body (Autodesk Fusion 360 design; units mm, degrees)
Autodesk Fusion 360 part; units mm, degrees
sketch "스케치1" plane through (0, 0, 0) normal (0, 1, 0) x (1, 0, 0)
  line L0 (0, 0) -> (100, 0)
  line L1 (100, 0) -> (100, -50)
  line L2 (100, -50) -> (0, -50)
  line L3 (0, -50) -> (0, 0)
  dimension "d1" = 100
  dimension "d2" = 50
  constraint horizontal L0
  constraint vertical L1
  constraint horizontal L2
  constraint vertical L3
  constraint coincident L0.start L3.end
  measures "d1" distance of L0.start L0.end
  measures "d2" distance of L0.start L2.end
extrude "돌출1" add sketch "스케치1" along normal blind 4.5 in component "Component"
sketch "스케치2" plane through (0, 0, 0) normal (0, -1, 0) x (1, 0, 0)
  line L0 (100, 50) -> (0, 50)
  line L1 (0, 50) -> (0, 0)
  line L2 (0, 0) -> (100, 0)
  line L3 (100, 0) -> (100, 50)
  circle A0 centre (5, 25) radius 1.5
  circle A1 centre (67, 25) radius 1.5
  circle A2 centre (29.8, 25) radius 1.5
  circle A3 centre (42.2, 25) radius 1.5
  line L4 (72, 50) -> (72, 0)
  dimension "d5" = 3
  dimension "d6" = 5
  dimension "d7" = 25
  dimension "d8" = 3
  dimension "d9" = 62
  dimension "d10" = 3
  dimension "d11" = 24.8
  dimension "d12" = 3
  dimension "d13" = 24.8
  dimension "d14" = 5
  constraint horizontal A0.centre A2.centre
  constraint coincident L0 L4.start
  constraint coincident L2 L4.end
  constraint perpendicular L2 L4
  measures "d5" diameter of A0
  measures "d6" distance of L1 A0.centre
  measures "d7" distance of L2 A0.centre
  measures "d8" diameter of A1
  measures "d9" distance of A0.centre A1.centre
  measures "d10" diameter of A2
  measures "d11" distance of A0.centre A2.centre
  measures "d12" diameter of A3
  measures "d13" distance of A1.centre A3.centre
  measures "d14" distance of A1.centre L4
extrude "돌출2" cut sketch "스케치2" against normal blind 4.5 contours A0 | A1 | A2 | A3 in component "Component"
extrude "돌출3" cut sketch "스케치2" against normal blind 100 contours L0 L2 L3 L4 in component "Component"
sketch "스케치3" plane through (0, 58.5, 0) normal (0, -1, 0) x (1, 0, 0)
  line L0 (72, 0) -> (72, 50)
  line L1 (72, 50) -> (0, 50)
  line L2 (0, 50) -> (0, 0)
  line L3 (0, 0) -> (72, 0)
  circle A0 centre (67, 25) radius 1.5
  circle A1 centre (5, 25) radius 1.5
  circle A2 centre (42.2, 25) radius 1.5
  circle A3 centre (29.8, 25) radius 1.5
  line L4 (67, 25) -> (73.125, 35.6088)
  line L5 (67, 25) -> (79.25, 25) construction
  line L6 (67, 25) -> (76.875, 7.896)
  line L7 (67, 25) -> (86.75, 25) construction
  line L8 (67, 25) -> (67, 5.25)
  line L9 (67, 25) -> (67, 37.25)
  line L10 (67, 25) -> (51, 25)
  arc A4 (67, 37.25) -> (67, 5.25) centre (66.5605, 21.25) ccw
  circle A5 centre (67, 25) radius 12.25
  circle A6 centre (67, 25) radius 19.75
  dimension "d19" = 60
  dimension "d20" = 12.25
  dimension "d21" = 60
  dimension "d22" = 19.75
  dimension "d23" = 19.75
  dimension "d24" = 12.25
  dimension "d25" = 16
  constraint horizontal L5
  constraint coincident A0.centre L4.start
  constraint horizontal L7
  constraint perpendicular L5 L8
  constraint perpendicular L5 L9
  constraint perpendicular L8 L10
  constraint coincident L10.end A4
  constraint coincident L4.end A5
  constraint concentric A5 A6
  constraint coincident L6.end A6
  measures "d19" angle of L4 L5
  measures "d20" distance of A0.centre L4.end
  measures "d21" angle of L6 L7
  measures "d22" distance of A0.centre L6.end
  measures "d23" distance of A0.centre L8.end
  measures "d24" distance of A0.centre L9.end
  measures "d25" distance of A0.centre L10.end
extrude "돌출1'" [suppressed] in component "Component'"
sketch "스케치4" plane through (0, 53, 0) normal (0, -1, 0) x (1, 0, 0)
  circle A0 centre (67, 25) radius 1.5
  arc A1 (73.125, 14.3912) -> (67, 37.25) centre (67, 25) ccw
  arc A2 (67, 37.25) -> (62.4338, 5.7851) centre (66.5605, 21.25) ccw
  arc A3 (62.4338, 5.7851) -> (76.875, 7.896) centre (67, 25) ccw
  line L0 (76.875, 7.896) -> (73.125, 14.3912)
  line L1 (67, 37.25) -> (66, 37.25)
  line L2 (66, 37.25) -> (66, 38.25)
  line L3 (66, 38.25) -> (67, 38.25)
  line L4 (67, 38.25) -> (67, 37.25)
  line L5 (67, 37.25) -> (68, 37.25)
  line L6 (68, 37.25) -> (68, 38.25)
  line L7 (68, 38.25) -> (67, 38.25)
  line L8 (67, 38.25) -> (67, 37.25)
  line L9 (66, 38.25) -> (68, 38.25)
  line L10 (68, 38.25) -> (68, 36.25)
  line L11 (68, 36.25) -> (66, 36.25)
  line L12 (66, 36.25) -> (66, 38.25)
  dimension "d28" = 1
  dimension "d29" = 1
  dimension "d30" = 1
  dimension "d31" = 2
  dimension "d32" = 2
  constraint horizontal L1
  constraint vertical L2
  constraint horizontal L3
  constraint vertical L4
  constraint coincident A1.end A2.start
  constraint horizontal L5
  constraint vertical L6
  constraint horizontal L7
  constraint vertical L8
  constraint horizontal L9
  constraint vertical L10
  constraint horizontal L11
  constraint vertical L12
  measures "d28" distance of A1.end L1.end
  measures "d29" distance of A1.end L3.end
  measures "d30" distance of A1.end L3.end
  measures "d31" distance of L2.end L6.end
  measures "d32" distance of L2.end L11.end
sketch "스케치5" plane through (0, 0, 50) normal (0, 0, 1) x (-1, 0, 0)
  line L0 (-72, -58.5) -> (-72, -63)
  line L1 (-72, -63) -> (0, -63)
  line L2 (0, -63) -> (0, -58.5)
  line L3 (0, -58.5) -> (-72, -58.5)
  line L4 (0, -63) -> (-20, -63)
  line L5 (-20, -63) -> (-20, 9)
  line L6 (-20, 9) -> (0, 9)
  line L7 (0, 9) -> (0, -63)
  line L8 (-72, -63) -> (-52, -63)
  line L9 (-52, -63) -> (-52, 9)
  line L10 (-52, 9) -> (-72, 9)
  line L11 (-72, 9) -> (-72, -63)
  dimension "d33" = 20
  dimension "d34" = 72
  dimension "d35" = 20
  dimension "d36" = 72
  constraint horizontal L4
  constraint vertical L5
  constraint horizontal L6
  constraint vertical L7
  constraint coincident L1.end L2.start
  constraint horizontal L8
  constraint vertical L9
  constraint horizontal L10
  constraint vertical L11
  constraint coincident L0.end L1.start
  measures "d33" distance of L1.end L4.end
  measures "d34" distance of L1.end L6.end
  measures "d35" distance of L0.end L8.end
  measures "d36" distance of L0.end L10.end
extrude "돌출1''" [suppressed] in component "Component''"
sketch "스케치6" plane through (0, -55.5322, 0) normal (0, 1, 0) x (-1, 0, 0)
  arc A0 (-21.5259, 27.2332) -> (-21.5259, 28.3332) centre (-20.5733, 27.7832) ccw
  line L0 (-21.5259, 27.2332) -> (-22.7233, 27.2332)
  line L1 (-22.7233, 27.2332) -> (-22.7233, 22.5332)
  arc A1 (-22.7233, 22.5332) -> (-21.8733, 21.6832) centre (-21.8733, 22.5332) ccw
  line L2 (-21.8733, 21.6832) -> (-17.0733, 21.6832)
  arc A2 (-17.9233, 22.5332) -> (-17.0733, 21.6832) centre (-17.0733, 22.5332) ccw
  line L3 (-17.9233, 22.5332) -> (-17.9233, 33.0332)
  arc A3 (-17.0733, 33.8832) -> (-17.9233, 33.0332) centre (-17.0733, 33.0332) ccw
  line L4 (-17.0733, 33.8832) -> (-21.8733, 33.8832)
  arc A4 (-21.8733, 33.8832) -> (-22.7233, 33.0332) centre (-21.8733, 33.0332) ccw
  line L5 (-22.7233, 33.0332) -> (-22.7233, 28.3332)
  line L6 (-22.7233, 28.3332) -> (-21.5259, 28.3332)
  line L7 (14.3767, 39.8832) -> (-27.7233, 39.8832)
  line L8 (-27.7233, 39.8832) -> (-27.7233, 15.6832)
  line L9 (-27.7233, 15.6832) -> (14.3767, 15.6832)
  line L10 (14.3767, 15.6832) -> (14.3767, 39.8832)
  line L11 (8.5267, 33.8832) -> (3.7267, 33.8832)
  line L12 (9.3767, 22.5332) -> (9.3767, 27.2332)
  line L13 (3.7267, 21.6832) -> (8.5267, 21.6832)
  line L14 (4.6267, 33.8832) -> (-17.964, 33.8832)
  line L15 (-17.964, 33.8832) -> (-17.964, 21.6832)
  line L16 (-17.964, 21.6832) -> (4.6267, 21.6832)
  line L17 (4.6267, 21.6832) -> (4.6267, 33.8832)
  point P0 (4.6267, 33.8832)
  point P1 (4.5189, 21.6832)
  point P2 (-18.0719, 33.8832)
  point P3 (-17.964, 21.6832)
  dimension "d39" = 6
  dimension "d40" = 5
  dimension "d41" = 6
  dimension "d42" = 5
  dimension "d43" = 0.9
  constraint horizontal L7
  constraint vertical L8
  constraint horizontal L9
  constraint vertical L10
  constraint coincident L11 P0
  constraint coincident L13 P1
  constraint coincident L4 P2
  constraint coincident L2 P3
  constraint horizontal L14
  constraint vertical L15
  constraint horizontal L16
  constraint vertical L17
  constraint coincident P3 L15.end
  constraint coincident P0 L14.start
  measures "d39" distance of L7 L11
  measures "d40" distance of L10 L12
  measures "d41" distance of L9 L13
  measures "d42" distance of L1.end L8
  measures "d43" distance of L11.end P0
extrude "돌출1'''" [suppressed] in component "Component'''"
sketch "스케치7" plane through (0, -9, 0) normal (0, -1, 0) x (1, 0, 0)
  line L0 (72, 0) -> (72, 50)
  line L1 (72, 50) -> (0, 50)
  line L2 (0, 50) -> (0, 0)
  line L3 (0, 0) -> (72, 0)
  circle A0 centre (67, 25) radius 1.5
  circle A1 centre (5, 25) radius 1.5
  circle A2 centre (42.2, 25) radius 1.5
  circle A3 centre (29.8, 25) radius 1.5
  circle A4 centre (5, 25) radius 2
  circle A5 centre (29.8, 25) radius 2
  circle A6 centre (42.2, 25) radius 2
  circle A7 centre (67, 25) radius 2
  dimension "d46" = 4
  dimension "d47" = 4
  dimension "d48" = 4
  dimension "d49" = 4
  constraint concentric A1 A4
  constraint concentric A3 A5
  constraint concentric A2 A6
  constraint concentric A0 A7
  measures "d46" diameter of A4
  measures "d47" diameter of A5
  measures "d48" diameter of A6
  measures "d49" diameter of A7
extrude "돌출4" [suppressed] in component "Component"
sketch "스케치8" plane through (0, 51.75, 0) normal (0, -1, 0) x (1, 0, 0)
  circle A0 centre (67, 25) radius 1.5
  arc A1 (73.125, 14.3912) -> (67, 37.25) centre (67, 25) ccw
  arc A2 (67, 37.25) -> (62.4338, 5.7851) centre (66.5605, 21.25) ccw
  arc A3 (62.4338, 5.7851) -> (76.875, 7.896) centre (67, 25) ccw
  line L0 (76.875, 7.896) -> (73.125, 14.3912)
  circle A4 centre (67, 25) radius 2
  dimension "d52" = 4
  constraint concentric A0 A4
  measures "d52" diameter of A4
extrude "돌출2'" [suppressed] in component "Component'"
sketch "스케치9" plane through (0, -42.0822, 0) normal (0, 1, 0) x (-1, 0, 0)
  line L0 (0.3767, 21.3332) -> (0.3767, 24.9036)
  arc A0 (0.3767, 24.9036) -> (0.6858, 25.1332) centre (-1.5233, 27.7832) ccw
  line L1 (0.6858, 25.1332) -> (12.6359, 25.7862)
  arc A1 (12.6359, 25.7862) -> (12.6359, 29.7802) centre (12.5267, 27.7832) ccw
  line L2 (12.6359, 29.7802) -> (0.6858, 30.4332)
  arc A2 (0.6858, 30.4332) -> (0.3767, 30.6629) centre (-1.5233, 27.7832) ccw
  line L3 (0.3767, 30.6629) -> (0.3767, 34.2332)
  arc A3 (0.3767, 34.2332) -> (-3.4233, 34.2332) centre (-1.5233, 34.2332) ccw
  line L4 (-3.4233, 34.2332) -> (-3.4233, 31.0786)
  line L5 (-3.4233, 31.0786) -> (-18.1496, 29.7754)
  arc A4 (-18.1496, 29.7754) -> (-18.1496, 25.791) centre (-17.9733, 27.7832) ccw
  line L6 (-18.1496, 25.791) -> (-3.4233, 24.4879)
  line L7 (-3.4233, 24.4879) -> (-3.4233, 21.3332)
  arc A5 (-3.4233, 21.3332) -> (0.3767, 21.3332) centre (-1.5233, 21.3332) ccw
  circle A6 centre (-16.3733, 27.7832) radius 0.6
  circle A7 centre (-18.3733, 27.7832) radius 0.6
  circle A8 centre (-14.3733, 27.7832) radius 0.6
  circle A9 centre (-12.3733, 27.7832) radius 0.6
  circle A10 centre (-10.3733, 27.7832) radius 0.6
  circle A11 centre (-8.3733, 27.7832) radius 0.6
  circle A12 centre (-6.3733, 27.7832) radius 0.6
  circle A13 centre (2.9267, 27.7832) radius 0.6
  circle A14 centre (4.9267, 27.7832) radius 0.6
  circle A15 centre (6.9267, 27.7832) radius 0.6
  circle A16 centre (8.9267, 27.7832) radius 0.6
  circle A17 centre (12.9267, 27.7832) radius 0.6
  circle A18 centre (10.9267, 27.7832) radius 0.6
  circle A19 centre (-1.5233, 27.7832) radius 2.3
  circle A20 centre (-1.5233, 23.3332) radius 0.6
  circle A21 centre (-1.5233, 21.3332) radius 0.6
  circle A22 centre (-1.5233, 32.2332) radius 0.6
  circle A23 centre (-1.5233, 34.2332) radius 0.6
  line L8 (-21.5233, 37.7832) -> (18.4767, 37.7832)
  line L9 (18.4767, 37.7832) -> (18.4767, 17.7832)
  line L10 (18.4767, 17.7832) -> (-21.5233, 17.7832)
  line L11 (-21.5233, 17.7832) -> (-21.5233, 37.7832)
  line L12 (-21.5233, 37.7832) -> (18.4767, 17.7832) construction
  line L13 (18.4767, 37.7832) -> (-21.5233, 17.7832) construction
  line L14 (3.4767, 10.2832) -> (-6.5233, 10.2832)
  line L15 (-6.5233, 10.2832) -> (-6.5233, 45.2832)
  line L16 (-6.5233, 45.2832) -> (3.4767, 45.2832)
  line L17 (3.4767, 45.2832) -> (3.4767, 10.2832)
  line L18 (3.4767, 10.2832) -> (-6.5233, 45.2832) construction
  line L19 (-6.5233, 10.2832) -> (3.4767, 45.2832) construction
  circle A24 centre (-1.5233, 27.7832) radius 2
  circle A25 centre (-1.5233, 15.1832) radius 2
  circle A26 centre (-1.5233, 40.3832) radius 2
  point P0 (-1.5233, 27.7832)
  point P1 (-1.5233, 27.7832)
  point P2 (-1.5233, 21.3332)
  dimension "d55" = 40
  dimension "d56" = 20
  dimension "d57" = 10
  dimension "d58" = 35
  dimension "d59" = 4
  dimension "d60" = 4
  dimension "d61" = 4
  dimension "d62" = 12.6
  dimension "d63" = 12.6
  constraint horizontal L8
  constraint perpendicular L8 L9
  constraint parallel L8 L10
  constraint parallel L9 L11
  constraint coincident L12 P1
  constraint coincident L13 P1
  constraint coincident P1 P0
  constraint horizontal L14
  constraint perpendicular L14 L15
  constraint parallel L14 L16
  constraint parallel L15 L17
  constraint coincident L18 P1
  constraint coincident L19 P1
  constraint concentric A0 A24
  constraint vertical A25.centre P2
  constraint vertical P1 A26.centre
  measures "d55" distance of L9.end L10.end
  measures "d56" distance of L8.end L9.end
  measures "d57" distance of L15.end L16.end
  measures "d58" distance of L14.end L15.end
  measures "d59" diameter of A24
  measures "d60" diameter of A25
  measures "d61" diameter of A26
  measures "d62" distance of P1 A26.centre
  measures "d63" distance of P1 A25.centre
extrude "돌출1''''" [suppressed] in component "Component''''"
sketch "스케치10" plane through (0, -37.5822, 0) normal (0, 1, 0) x (-1, 0, 0)
  arc A0 (-3.4233, 21.3332) -> (0.3767, 21.3332) centre (-1.5233, 21.3332) ccw
  line L0 (-3.4233, 21.3332) -> (-3.4233, 24.4879)
  line L1 (-3.4233, 24.4879) -> (-18.1496, 25.791)
  arc A1 (-18.1496, 29.7754) -> (-18.1496, 25.791) centre (-17.9733, 27.7832) ccw
  line L2 (-18.1496, 29.7754) -> (-3.4233, 31.0786)
  line L3 (-3.4233, 31.0786) -> (-3.4233, 34.2332)
  arc A2 (0.3767, 34.2332) -> (-3.4233, 34.2332) centre (-1.5233, 34.2332) ccw
  line L4 (0.3767, 34.2332) -> (0.3767, 30.6629)
  arc A3 (0.6858, 30.4332) -> (0.3767, 30.6629) centre (-1.5233, 27.7832) ccw
  line L5 (0.6858, 30.4332) -> (12.6359, 29.7802)
  arc A4 (12.6359, 25.7862) -> (12.6359, 29.7802) centre (12.5267, 27.7832) ccw
  line L6 (12.6359, 25.7862) -> (0.6858, 25.1332)
  arc A5 (0.3767, 24.9036) -> (0.6858, 25.1332) centre (-1.5233, 27.7832) ccw
  line L7 (0.3767, 24.9036) -> (0.3767, 21.3332)
  circle A6 centre (-1.5233, 15.1832) radius 2
  circle A7 centre (-1.5233, 40.3832) radius 2
  line L8 (3.4767, 45.2832) -> (-6.5233, 45.2832)
  line L9 (-6.5233, 45.2832) -> (-6.5233, 37.7832)
  line L10 (-6.5233, 37.7832) -> (-21.5233, 37.7832)
  line L11 (-21.5233, 37.7832) -> (-21.5233, 17.7832)
  line L12 (-21.5233, 17.7832) -> (-6.5233, 17.7832)
  line L13 (-6.5233, 17.7832) -> (-6.5233, 10.2832)
  line L14 (-6.5233, 10.2832) -> (3.4767, 10.2832)
  line L15 (3.4767, 10.2832) -> (3.4767, 17.7832)
  line L16 (3.4767, 17.7832) -> (18.4767, 17.7832)
  line L17 (18.4767, 17.7832) -> (18.4767, 37.7832)
  line L18 (18.4767, 37.7832) -> (3.4767, 37.7832)
  line L19 (3.4767, 37.7832) -> (3.4767, 45.2832)
  line L20 (-6.5233, 45.2832) -> (3.4767, 45.2832)
  line L21 (3.4767, 45.2832) -> (3.4767, 10.2832)
  line L22 (3.4767, 10.2832) -> (-6.5233, 10.2832)
  line L23 (-6.5233, 10.2832) -> (-6.5233, 45.2832)
  circle A8 centre (-1.5233, 40.3832) radius 2
  circle A9 centre (-1.5233, 15.1832) radius 2
  constraint horizontal L20
  constraint vertical L21
  constraint horizontal L22
  constraint vertical L23
  constraint coincident L14.end L15.start
  constraint coincident L8.end L9.start
  constraint concentric A7 A8
  constraint concentric A6 A9
extrude "돌출1'''''" [suppressed] in component "Component'''''"
sketch "스케치11" plane through (0, -44.0822, 0) normal (0, -1, 0) x (1, 0, 0)
  arc A0 (-0.3767, 21.3332) -> (3.4233, 21.3332) centre (1.5233, 21.3332) ccw
  line L0 (-0.3767, 21.3332) -> (-0.3767, 24.9036)
  arc A1 (-0.6858, 25.1332) -> (-0.3767, 24.9036) centre (1.5233, 27.7832) ccw
  line L1 (-0.6858, 25.1332) -> (-12.6359, 25.7862)
  arc A2 (-12.6359, 29.7802) -> (-12.6359, 25.7862) centre (-12.5267, 27.7832) ccw
  line L2 (-12.6359, 29.7802) -> (-0.6858, 30.4332)
  arc A3 (-0.3767, 30.6629) -> (-0.6858, 30.4332) centre (1.5233, 27.7832) ccw
  line L3 (-0.3767, 30.6629) -> (-0.3767, 34.2332)
  arc A4 (3.4233, 34.2332) -> (-0.3767, 34.2332) centre (1.5233, 34.2332) ccw
  line L4 (3.4233, 34.2332) -> (3.4233, 31.0786)
  line L5 (3.4233, 31.0786) -> (18.1496, 29.7754)
  arc A5 (18.1496, 25.791) -> (18.1496, 29.7754) centre (17.9733, 27.7832) ccw
  line L6 (18.1496, 25.791) -> (3.4233, 24.4879)
  line L7 (3.4233, 24.4879) -> (3.4233, 21.3332)
  circle A6 centre (1.5233, 15.1832) radius 2
  circle A7 centre (1.5233, 40.3832) radius 2
  line L8 (6.5233, 45.2832) -> (-3.4767, 45.2832)
  line L9 (-3.4767, 45.2832) -> (-3.4767, 37.7832)
  line L10 (-3.4767, 37.7832) -> (-18.4767, 37.7832)
  line L11 (-18.4767, 37.7832) -> (-18.4767, 17.7832)
  line L12 (-18.4767, 17.7832) -> (-3.4767, 17.7832)
  line L13 (-3.4767, 17.7832) -> (-3.4767, 10.2832)
  line L14 (-3.4767, 10.2832) -> (6.5233, 10.2832)
  line L15 (6.5233, 10.2832) -> (6.5233, 17.7832)
  line L16 (6.5233, 17.7832) -> (21.5233, 17.7832)
  line L17 (21.5233, 17.7832) -> (21.5233, 37.7832)
  line L18 (21.5233, 37.7832) -> (6.5233, 37.7832)
  line L19 (6.5233, 37.7832) -> (6.5233, 45.2832)
  line L20 (-18.4767, 37.7832) -> (21.5233, 37.7832)
  line L21 (21.5233, 37.7832) -> (21.5233, 17.7832)
  line L22 (21.5233, 17.7832) -> (-18.4767, 17.7832)
  line L23 (-18.4767, 17.7832) -> (-18.4767, 37.7832)
  circle A8 centre (1.5233, 27.7832) radius 3.45
  constraint horizontal L20
  constraint vertical L21
  constraint horizontal L22
  constraint vertical L23
  constraint coincident L16.end L17.start
  constraint coincident L10.end L11.start
  constraint concentric A1 A8
  constraint coincident L0.end A8
extrude "돌출1''''''" [suppressed] in component "3T"
sketch "스케치12" plane through (0, -44.0822, 0) normal (0, -1, 0) x (1, 0, 0)
  arc A0 (-0.3767, 21.3332) -> (3.4233, 21.3332) centre (1.5233, 21.3332) ccw
  line L0 (-0.3767, 21.3332) -> (-0.3767, 24.9036)
  arc A1 (-0.6858, 25.1332) -> (-0.3767, 24.9036) centre (1.5233, 27.7832) ccw
  line L1 (-0.6858, 25.1332) -> (-12.6359, 25.7862)
  arc A2 (-12.6359, 29.7802) -> (-12.6359, 25.7862) centre (-12.5267, 27.7832) ccw
  line L2 (-12.6359, 29.7802) -> (-0.6858, 30.4332)
  arc A3 (-0.3767, 30.6629) -> (-0.6858, 30.4332) centre (1.5233, 27.7832) ccw
  line L3 (-0.3767, 30.6629) -> (-0.3767, 34.2332)
  arc A4 (3.4233, 34.2332) -> (-0.3767, 34.2332) centre (1.5233, 34.2332) ccw
  line L4 (3.4233, 34.2332) -> (3.4233, 31.0786)
  line L5 (3.4233, 31.0786) -> (18.1496, 29.7754)
  arc A5 (18.1496, 25.791) -> (18.1496, 29.7754) centre (17.9733, 27.7832) ccw
  line L6 (18.1496, 25.791) -> (3.4233, 24.4879)
  line L7 (3.4233, 24.4879) -> (3.4233, 21.3332)
  circle A6 centre (1.5233, 15.1832) radius 2
  circle A7 centre (1.5233, 40.3832) radius 2
  line L8 (6.5233, 45.2832) -> (-3.4767, 45.2832)
  line L9 (-3.4767, 45.2832) -> (-3.4767, 37.7832)
  line L10 (-3.4767, 37.7832) -> (-18.4767, 37.7832)
  line L11 (-18.4767, 37.7832) -> (-18.4767, 17.7832)
  line L12 (-18.4767, 17.7832) -> (-3.4767, 17.7832)
  line L13 (-3.4767, 17.7832) -> (-3.4767, 10.2832)
  line L14 (-3.4767, 10.2832) -> (6.5233, 10.2832)
  line L15 (6.5233, 10.2832) -> (6.5233, 17.7832)
  line L16 (6.5233, 17.7832) -> (21.5233, 17.7832)
  line L17 (21.5233, 17.7832) -> (21.5233, 37.7832)
  line L18 (21.5233, 37.7832) -> (6.5233, 37.7832)
  line L19 (6.5233, 37.7832) -> (6.5233, 45.2832)
  circle A8 centre (-14.4767, 33.7832) radius 2
  circle A9 centre (17.5233, 21.7832) radius 2
  circle A10 centre (17.5233, 33.7832) radius 2
  circle A11 centre (-14.4767, 21.7832) radius 2
  dimension "d72" = 4
  dimension "d73" = 4
  dimension "d74" = 4
  dimension "d75" = 4
  dimension "d76" = 4
  dimension "d77" = 4
  dimension "d78" = 4
  dimension "d79" = 4
  dimension "d80" = 4
  dimension "d81" = 4
  dimension "d82" = 4
  dimension "d83" = 4
  measures "d72" diameter of A8
  measures "d73" distance of L10 A8.centre
  measures "d74" distance of L11 A8.centre
  measures "d75" diameter of A9
  measures "d76" distance of L16 A9.centre
  measures "d77" distance of L17 A9.centre
  measures "d78" diameter of A10
  measures "d79" distance of L17 A10.centre
  measures "d80" distance of L18 A10.centre
  measures "d81" diameter of A11
  measures "d82" distance of L12 A11.centre
  measures "d83" distance of L11 A11.centre
extrude "돌출2''" [suppressed] in component "Component''''"
extrude "돌출2'''" [no effect] in component "3T"
extrude "돌출2''''" [suppressed] in component "Component'''"
sketch "스케치13" plane through (0, 2.25, 0) normal (0, 1, 0) x (-1, 0, 0)
  circle A0 centre (-67, 25) radius 2
  arc A1 (-67, 37.25) -> (-73.125, 14.3912) centre (-67, 25) ccw
  line L0 (-73.125, 14.3912) -> (-76.875, 7.896)
  arc A2 (-76.875, 7.896) -> (-62.4338, 5.7851) centre (-67, 25) ccw
  arc A3 (-62.4338, 5.7851) -> (-67, 37.25) centre (-66.5605, 21.25) ccw
sketch "스케치14" plane through (0, 51.75, 0) normal (0, -1, 0) x (1, 0, 0)
  circle A0 centre (67, 25) radius 2
  arc A1 (73.125, 14.3912) -> (67, 37.25) centre (67, 25) ccw
  arc A2 (67, 37.25) -> (62.4338, 5.7851) centre (66.5605, 21.25) ccw
  arc A3 (62.4338, 5.7851) -> (76.875, 7.896) centre (67, 25) ccw
  line L0 (76.875, 7.896) -> (73.125, 14.3912)
  circle A4 centre (67, 25) radius 4.5
  circle A5 centre (67, 25) radius 2.05
  dimension "d90" = 9
  dimension "d91" = 4.1
  constraint concentric A0 A4
  constraint concentric A0 A5
  measures "d90" diameter of A4
  measures "d91" diameter of A5
extrude "돌출1'''''''" [suppressed] in component "Component''''''"
sketch "스케치15" plane through (0, 51.75, 0) normal (0, 1, 0) x (-1, 0, 0)
  circle A0 centre (-67, 25) radius 2.05
  circle A1 centre (-67, 25) radius 4.5
  line L0 (-57, 22) -> (-77, 22)
  line L1 (-77, 22) -> (-77, 28)
  line L2 (-77, 28) -> (-57, 28)
  line L3 (-57, 28) -> (-57, 22)
  line L4 (-57, 22) -> (-77, 28) construction
  line L5 (-77, 22) -> (-57, 28) construction
  circle A2 centre (-74, 25) radius 2.05
  circle A3 centre (-60, 25) radius 2.05
  point P0 (-67, 25)
  dimension "d94" = 20
  dimension "d95" = 6
  dimension "d96" = 4.1
  dimension "d97" = 4.1
  dimension "d98" = 7
  dimension "d99" = 7
  constraint horizontal L0
  constraint perpendicular L0 L1
  constraint parallel L0 L2
  constraint parallel L1 L3
  constraint coincident L4 P0
  constraint coincident L5 P0
  constraint coincident P0 A0.centre
  constraint horizontal P0 A2.centre
  constraint horizontal P0 A3.centre
  measures "d94" distance of L1.end L2.end
  measures "d95" distance of L0.end L1.end
  measures "d96" diameter of A2
  measures "d97" diameter of A3
  measures "d98" distance of P0 A2.centre
  measures "d99" distance of P0 A3.centre
extrude "돌출2'''''" [suppressed] in component "Component''''''"
sketch "스케치16" plane through (0, 47.25, 0) normal (0, -1, 0) x (1, 0, 0)
  circle A0 centre (67, 25) radius 2.05
  circle A1 centre (67, 25) radius 4.5
  line L0 (70, 35) -> (64, 35)
  line L1 (64, 35) -> (64, 15)
  line L2 (64, 15) -> (70, 15)
  line L3 (70, 15) -> (70, 35)
  line L4 (70, 35) -> (64, 15) construction
  line L5 (64, 35) -> (70, 15) construction
  circle A2 centre (67, 32) radius 2.05
  circle A3 centre (67, 18) radius 2.05
  point P0 (67, 25)
  dimension "d102" = 6
  dimension "d103" = 4.1
  dimension "d104" = 4.1
  dimension "d105" = 20
  dimension "d106" = 7
  dimension "d107" = 7
  constraint horizontal L0
  constraint perpendicular L0 L1
  constraint parallel L0 L2
  constraint parallel L1 L3
  constraint coincident L4 P0
  constraint coincident L5 P0
  constraint coincident P0 A0.centre
  measures "d102" distance of L1.end L2.end
  measures "d103" diameter of A2
  measures "d104" diameter of A3
  measures "d105" distance of L0 L2
  measures "d106" distance of P0 A2.centre
  measures "d107" distance of P0 A3.centre
extrude "돌출3'" [suppressed] in component "Component''''''"
component "Component" placed x (1, 0, 0) y (0, 1, 0) z (0, 0, 1) at (0, -9, 0)
component "Component" placed x (1, 0, 0) y (0, 1, 0) z (0, 0, 1) at (0, 58.5, 0)
